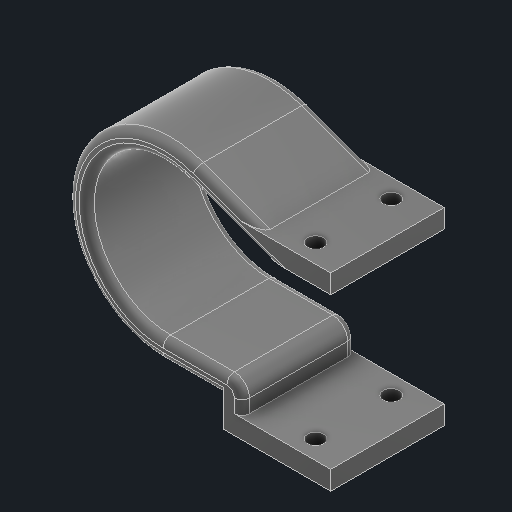
# Autodesk Inventor part: Calço motor Pittman
Saved by Autodesk Inventor 2026.1 (Build 301233000, 233)
## iProperties
Created: 2025-01-07
Part Number: Calço motor Pittman
Material: ABS plástico
Document SubType Name: Modeling
Designer: Cliente
Density: 0.958837 g/cm^3
Appearance: Suave - Branco
Mass: 23.36 g
Surface Area: 117.987 cm^2
Volume: 24.3629 cm^3
Author: Cliente
Autodesk Inventor part; units mm, degrees
ref_plane "YZ Plane" through (0, 0, 0) normal (1, 0, 0) x (0, 1, 0)
ref_plane "XZ Plane" through (0, 0, 0) normal (0, 1, 0) x (-1, 0, 0)
ref_plane "Plano de trabalho1" through (0, 0, 0) normal (0, 0, 1) x (1, 0, 0)
sketch "Esboço1" plane through (0, 0, 0) normal (0, 0, 1) x (1, 0, 0)
  circle A0 centre (0, 0) radius 20
  line L0 (45.35, 7) -> (45.35, 11.7)
  arc A1 (45.35, 11.7) -> (44.85, 12.2) centre (44.85, 11.7) ccw
  line L1 (44.85, 12.2) -> (40.15, 12.2)
  line L2 (40.15, 12.2) -> (38.35, 10.4)
  line L3 (38.35, 10.4) -> (40.85, 10.4)
  line L4 (40.85, 10.4) -> (40.85, 8.689949)
  line L5 (40.85, 8.689949) -> (38.360051, 6.2)
  line L6 (38.360051, 6.2) -> (32.339949, 6.2)
  line L7 (32.339949, 6.2) -> (29.85, 8.689949)
  line L8 (29.85, 8.689949) -> (29.85, 10.4)
  line L9 (29.85, 10.4) -> (32.35, 10.4)
  line L10 (32.35, 10.4) -> (30.55, 12.2)
  line L11 (30.55, 12.2) -> (25.85, 12.2)
  arc A2 (25.85, 12.2) -> (25.35, 11.7) centre (25.85, 11.7) ccw
  line L12 (25.35, 11.7) -> (25.35, 7)
  line L13 (25.35, 7) -> (27.15, 5.2)
  line L14 (27.15, 5.2) -> (27.15, 7.7)
  line L15 (27.15, 7.7) -> (28.860051, 7.7)
  line L16 (28.860051, 7.7) -> (31.35, 5.210051)
  line L17 (31.35, 5.210051) -> (31.35, -0.810051)
  line L18 (31.35, -0.810051) -> (28.860051, -3.3)
  line L19 (28.860051, -3.3) -> (27.15, -3.3)
  line L20 (27.15, -3.3) -> (27.15, -0.8)
  line L21 (27.15, -0.8) -> (25.35, -2.6)
  line L22 (25.35, -2.6) -> (25.35, -13)
  line L23 (25.35, -13) -> (27.15, -14.8)
  line L24 (27.15, -14.8) -> (27.15, -12.3)
  line L25 (27.15, -12.3) -> (28.860051, -12.3)
  line L26 (28.860051, -12.3) -> (31.35, -14.789949)
  line L27 (31.35, -14.789949) -> (31.35, -20.810051)
  line L28 (31.35, -20.810051) -> (28.860051, -23.3)
  line L29 (28.860051, -23.3) -> (27.15, -23.3)
  line L30 (27.15, -23.3) -> (27.15, -20.8)
  line L31 (27.15, -20.8) -> (25.35, -22.6)
  line L32 (25.35, -22.6) -> (25.35, -27.3)
  arc A3 (25.35, -27.3) -> (25.85, -27.8) centre (25.85, -27.3) ccw
  line L33 (25.85, -27.8) -> (30.55, -27.8)
  line L34 (30.55, -27.8) -> (32.35, -26)
  line L35 (32.35, -26) -> (29.85, -26)
  line L36 (29.85, -26) -> (29.85, -24.289949)
  line L37 (29.85, -24.289949) -> (32.339949, -21.8)
  line L38 (32.339949, -21.8) -> (38.360051, -21.8)
  line L39 (38.360051, -21.8) -> (40.85, -24.289949)
  line L40 (40.85, -24.289949) -> (40.85, -26)
  line L41 (40.85, -26) -> (38.35, -26)
  line L42 (38.35, -26) -> (40.15, -27.8)
  line L43 (40.15, -27.8) -> (44.85, -27.8)
  arc A4 (44.85, -27.8) -> (45.35, -27.3) centre (44.85, -27.3) ccw
  line L44 (45.35, -27.3) -> (45.35, -22.6)
  line L45 (45.35, -22.6) -> (43.55, -20.8)
  line L46 (43.55, -20.8) -> (43.55, -23.3)
  line L47 (43.55, -23.3) -> (41.839949, -23.3)
  line L48 (41.839949, -23.3) -> (39.35, -20.810051)
  line L49 (39.35, -20.810051) -> (39.35, -14.789949)
  line L50 (39.35, -14.789949) -> (41.839949, -12.3)
  line L51 (41.839949, -12.3) -> (43.55, -12.3)
  line L52 (43.55, -12.3) -> (43.55, -14.8)
  line L53 (43.55, -14.8) -> (45.35, -13)
  line L54 (45.35, -13) -> (45.35, -2.6)
  line L55 (45.35, -2.6) -> (43.55, -0.8)
  line L56 (43.55, -0.8) -> (43.55, -3.3)
  line L57 (43.55, -3.3) -> (41.839949, -3.3)
  line L58 (41.839949, -3.3) -> (39.35, -0.810051)
  line L59 (39.35, -0.810051) -> (39.35, 5.210051)
  line L60 (39.35, 5.210051) -> (41.839949, 7.7)
  line L61 (41.839949, 7.7) -> (43.55, 7.7)
  line L62 (43.55, 7.7) -> (43.55, 5.2)
  line L63 (43.55, 5.2) -> (45.35, 7)
  circle A5 centre (35.35, 2.2) radius 2.5
  circle A6 centre (35.35, -17.8) radius 2.5
  line L64 (27.15, -10.9) -> (27.15, -4.7)
  line L65 (27.15, -4.7) -> (29.439949, -4.7)
  line L66 (29.439949, -4.7) -> (32.339949, -1.8)
  line L67 (32.339949, -1.8) -> (38.360051, -1.8)
  line L68 (38.360051, -1.8) -> (41.260051, -4.7)
  line L69 (41.260051, -4.7) -> (43.55, -4.7)
  line L70 (43.55, -4.7) -> (43.55, -10.9)
  line L71 (43.55, -10.9) -> (41.260051, -10.9)
  line L72 (41.260051, -10.9) -> (38.360051, -13.8)
  line L73 (38.360051, -13.8) -> (32.339949, -13.8)
  line L74 (32.339949, -13.8) -> (29.439949, -10.9)
  line L75 (29.439949, -10.9) -> (27.15, -10.9)
  line L76 (26.35, 12.2) -> (44.35, 12.2)
  line L77 (44.35, 12.2) -> (44.35, 17.2)
  line L78 (44.35, 17.2) -> (26.35, 17.2)
  line L79 (26.35, 17.2) -> (26.35, 12.2)
  line L80 (26.35, 12.2) -> (44.35, 17.2) construction
  line L81 (44.35, 12.2) -> (26.35, 17.2) construction
  line L82 (26.35, -32.8) -> (44.35, -32.8)
  line L83 (44.35, -32.8) -> (44.35, -27.8)
  line L84 (44.35, -27.8) -> (26.35, -27.8)
  line L85 (26.35, -27.8) -> (26.35, -32.8)
  line L86 (26.35, -32.8) -> (44.35, -27.8) construction
  line L87 (44.35, -32.8) -> (26.35, -27.8) construction
  circle A7 centre (0, 0) radius 20.2
  circle A8 centre (0, 0) radius 25.2
  line L88 (26.35, 17.2) -> (8.650358, 23.668784)
  line L89 (26.35, 12.2) -> (-6.72188, 24.286958)
  line L90 (5.386905, 19.468468) -> (9.81406, 18.243479)
  line L91 (26.35, -27.8) -> (20.85, -27.8)
  line L92 (20.85, -27.8) -> (20.85, -20.2)
  line L93 (20.85, -20.2) -> (0, -20.2)
  line L94 (0, -25.2) -> (15.85, -25.2)
  line L95 (15.85, -25.2) -> (15.85, -32.8)
  line L96 (15.85, -32.8) -> (26.35, -32.8)
  point P0 (0, 0)
  point P1 (35.35, 14.7)
  point P2 (35.35, -30.3)
  point P3 (26.35, 12.2)
  point P4 (30.55, -27.8)
  point P5 (26.35, -27.8)
  point P6 (15.066519, -20.2)
  point P7 (20.798492, 14.228939)
  point P8 (40.15, 12.2)
  point P9 (22.049943, 12.2)
  point P10 (22.953867, 10.4)
  point P11 (13.735963, -21.127312)
  point P12 (21.904776, -12.458763)
  point P13 (24.116706, 7.309207)
  dimension "d0" = 18
  dimension "d1" = 5
  dimension "d2" = 18
  dimension "d3" = 5
  dimension "d4" = 0.2
  dimension "d5" = 5
  dimension "d6" = 5.5
  dimension "d8" = 5
  constraints: 42 end point, 5 horizontal, 5 midpoint, 5 parallel, 5 point on circle, 4 perpendicular, 4 tangent, 3 point on line, 2 centre point, 2 vertical alignment, 1 vertical
  measures "d0" distance of L78.end L77.end
  measures "d1" distance of L77.end L76.end
  measures "d2" distance of L84.end L83.end
  measures "d3" distance of L83.end L82.end
  measures "d4" radial gap between concentric circles of A0 A7
  measures "d5" radial gap between concentric circles of A7 A8
  measures "d6" distance of L84.end L91.end
  measures "d8" distance between parallel lines of L95 L92
extrude "Extrusão1" add sketch "Esboço1" along normal mid plane 30 contours L1 L76 L11 L79 L78 L77 | L79 L89 A8 L88 | A8 L89 | L89 L90 A7 L93 A8 | A8 L93 L92 L91 L33 L85 L96 L95 L94 | L85 L33 L84 L43 L83 L82 picked at (8.502755, -21.111636)
sketch "Esboço2" plane through (27.226913, 17.2, 15) normal (0, 1, 0) x (1, 0, 0)
  line L0 (-0.876913, 30) -> (-0.876913, 0)
  line L1 (17.123087, 0) -> (-0.876913, 0)
  line L2 (17.123087, 30) -> (17.123087, 0)
  line L3 (-0.876913, 30) -> (17.123087, 30)
  line L4 (8.123087, 5) -> (8.123087, 25)
  circle A0 centre (8.123087, 5) radius 2.15
  circle A1 centre (8.123087, 25) radius 2.15
  point P0 (8.123087, 15)
  point P1 (-0.876913, 15)
  point P2 (8.123087, 0)
  dimension "d19" = 20
  dimension "d20" = 4.3
  dimension "d21" = 4.3
  constraints: 3 midpoint, 2 centre point, 2 coincident, 2 end point, 1 horizontal alignment, 1 vertical, 1 vertical alignment
  measures "d19" distance of L4.start L4.end
  measures "d20" diameter of A0
  measures "d21" diameter of A1
extrude "Extrusão2" cut sketch "Esboço2" against normal through all contours A0 | A1
fillet "Arredondamento1" radius 4 1 edges at (20.85, -20.2, 0)
fillet "Arredondamento2" radius 2 18 edges at (7.6005, 18.856, 15) (8.425, -20.2, 15) (19.6784, -21.3716, 15) (20.85, -26, 15) (-20.0163, 2.7182, 15) (7.925, -25.2, 15) (17.5002, 20.4344, 15) (-24.8142, 4.3924, 15) (8.425, -20.2, -15) (19.6784, -21.3716, -15) (20.85, -26, -15) (7.6005, 18.856, -15) (-20.0163, 2.7182, -15) (17.5002, 20.4344, -15) (7.925, -25.2, -15) (-24.8142, 4.3924, -15) (18.082, 15.2217, -15) (18.082, 15.2217, 15)
